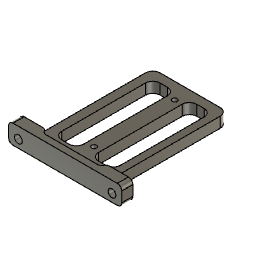
rs-25-5-90 (Autodesk Fusion 360 design; units mm, degrees)
Autodesk Fusion 360 part; units mm, degrees
mesh "Mesh1" [no effect]
sketch "Sketch1" plane through (0, 0, 0) normal (0, 0, 1) x (1, 0, 0)
  line L0 (25, 0) -> (-26, 0)
  line L1 (-26, 0) -> (-26, 78)
  line L2 (-26, 78) -> (25, 78)
  line L3 (25, 78) -> (25, 0)
  line L4 (-20, 5) -> (-5, 5)
  line L5 (-5, 5) -> (-5, 72)
  line L6 (-5, 72) -> (-20, 72)
  line L7 (-20, 72) -> (-20, 5)
  line L8 (0, 0) -> (0, 5) construction
  line L9 (20, 72) -> (20, 5)
  line L10 (5, 72) -> (20, 72)
  line L11 (5, 5) -> (5, 72)
  line L12 (20, 5) -> (5, 5)
  line L13 (0, 0) -> (0, 12) construction
  circle A0 centre (0, 12) radius 1.7
  line L14 (0, 12) -> (0, 39.5) construction
  line L15 (0, 39.5) -> (2, 39.5) construction
  circle A1 centre (0, 67) radius 1.7
  dimension "d1" = 51
  dimension "d2" = 78
  dimension "d3" = 67
  dimension "d4" = 12
  dimension "d5" = 3.4
  dimension "d6" = 27.5
  constraint horizontal L0
  constraint vertical L1
  constraint horizontal L2
  constraint vertical L3
  constraint horizontal L4
  constraint vertical L5
  constraint horizontal L6
  constraint vertical L7
  constraint coincident L8.start L13.start
  constraint perpendicular L0 L8
  constraint symmetric L4.start L8 L9.end
  constraint symmetric L4.end L8 L11.start
  constraint symmetric L5.end L8 L10.start
  constraint symmetric L6.end L8 L9.start
  constraint perpendicular L0 L13
  constraint coincident L13.end A0.centre
  constraint parallel L11 L14
  constraint perpendicular L14 L15
  constraint symmetric A0 L15 A1
  measures "d1" distance of L0.start L0.end
  measures "d2" distance of L0.start L2.end
  measures "d3" distance of L4.start L6.end
  measures "d4" distance of L8.start L13.end
  measures "d5" diameter of A0
  measures "d6" distance of L13.end L14.end
extrude "Extrude1" add sketch "Sketch1" along normal blind 7
sketch "Sketch2" plane through (0, 0, 0) normal (0, 1, 0) x (1, 0, 0)
  line L0 (38.4772, 0.1346) -> (-38.5893, 0.1346)
  line L1 (-38.5893, 0.1346) -> (-38.5893, -12.8654)
  line L2 (-38.5893, -12.8654) -> (38.4772, -12.8654)
  line L3 (38.4772, -12.8654) -> (38.4772, 0.1346)
  circle A0 centre (-31.8892, -5.2424) radius 2.65
  line L4 (0, 0) -> (0, -9) construction
  circle A1 centre (31.8892, -5.2424) radius 2.65
  dimension "d9" = 13
  dimension "d10" = 5.3
  constraint horizontal L0
  constraint vertical L1
  constraint horizontal L2
  constraint vertical L3
  constraint coincident L4.start origin
  constraint perpendicular L0 L4
  constraint symmetric A0 L4 A1
  measures "d9" distance of L0.end L1.end
  measures "d10" diameter of A0
extrude "Extrude2" add sketch "Sketch2" against normal blind 7.6
sketch "Sketch3" plane through (0, 0, 0) normal (0, 1, 0) x (-1, 0, 0)
  line L0 (-38.4772, 12.8654) -> (-38.4772, -0.1346)
  line L1 (-38.4772, -0.1346) -> (38.5893, -0.1346)
  line L2 (38.5893, -0.1346) -> (38.5893, 12.8654)
  line L3 (38.5893, 12.8654) -> (-38.4772, 12.8654)
  circle A0 centre (-31.8892, 5.2424) radius 2.65
  circle A1 centre (31.8892, 5.2424) radius 2.65
  line L4 (26, 7) -> (26, 0)
  line L5 (26, 0) -> (-25, 0)
  line L6 (-25, 0) -> (-25, 7)
  line L7 (-25, 7) -> (26, 7)
  circle A2 centre (-31.8892, 5.2424) radius 5.25
  line L8 (0, 0) -> (0, 11.9624) construction
  circle A3 centre (31.8892, 5.2424) radius 5.25
  line L9 (35.0019, 1.9981) -> (29.0019, 1.9981)
  line L10 (29.0019, 1.9981) -> (29.0019, -2.0108)
  line L11 (29.0019, -2.0108) -> (35.0019, -2.0108)
  line L12 (35.0019, -2.0108) -> (35.0019, 1.9981)
  line L13 (-35.0019, -2.0108) -> (-35.0019, 1.9981)
  line L14 (-35.0019, 1.9981) -> (-29.0019, 1.9981)
  line L15 (-29.0019, 1.9981) -> (-29.0019, -2.0108)
  line L16 (-29.0019, -2.0108) -> (-35.0019, -2.0108)
  point P0 (32.0019, -0.0064)
  dimension "d13" = 10.5
  dimension "d26" = 6
  constraint concentric A0 A2
  constraint coincident L8.start origin
  constraint perpendicular L7 L8
  constraint symmetric A2 L8 A3
  constraint perpendicular L9 L10
  constraint parallel L9 L11
  constraint parallel L10 L12
  constraint horizontal L9
  constraint coincident A3 P0
  constraint symmetric L8 L9.start L13.end
  constraint symmetric L8 L9.end L14.end
  constraint symmetric L8 L10.end L15.end
  constraint symmetric L8 L11.end L13.start
  measures "d13" diameter of A2
  measures "d26" distance of L10.end L11.end
extrude "Extrude6" cut sketch "Sketch3" against normal blind 3 contours L1 A2 L13 L15 | A2 L13 L14 L15 | L1 A3 L10 L12 | A3 L9 L10 L12 picked at (-32.1282, 1.3372) picked at (32.1282, 1.3372)
extrude "Extrude3" cut sketch "Sketch3" against normal blind 3 contours A2 L13 L14 L15 | A2 L13 L14 L15 | A3 L9 L10 L12 | A3 L9 L10 L12
sketch "Sketch4" plane through (0, 0, 0) normal (0, 0, -1) x (1, 0, 0)
  line L0 (20, -5) -> (20, -72)
  line L1 (20, -72) -> (5, -72)
  line L2 (5, -72) -> (5, -5)
  line L3 (5, -5) -> (20, -5)
  circle A0 centre (0, -67) radius 1.7
  line L4 (-20, -72) -> (-20, -5)
  line L5 (-20, -5) -> (-5, -5)
  line L6 (-5, -5) -> (-5, -72)
  line L7 (-5, -72) -> (-20, -72)
  circle A1 centre (0, -12) radius 1.7
  line L8 (-26, -78) -> (25, -78)
  line L9 (25, -78) -> (25, 0)
  line L10 (25, 0) -> (-26, 0)
  line L11 (-26, 0) -> (-26, -78)
  circle A2 centre (0, -67) radius 3.6
  line L12 (-3.0129, -39.5) -> (3.0263, -39.5) construction
  circle A3 centre (0, -12) radius 3.6
  point P0 (0, -39.5)
  dimension "d16" = 7.2
  dimension "d17" = 27.5
  constraint concentric A0 A2
  constraint horizontal L12
  constraint symmetric A2 L12 A3
  measures "d16" diameter of A2
  measures "d17" distance of A0.centre P0
extrude "Extrude4" cut sketch "Sketch4" against normal blind 3 contours A2 | A3
sketch "Sketch5" plane through (0, 0, 12.8654) normal (0, 0, 1) x (-1, 0, 0)
  line L0 (-38.4772, 0) -> (38.5893, 0)
  line L1 (38.5893, 0) -> (38.5893, 7.6)
  line L2 (38.5893, 7.6) -> (-38.4772, 7.6)
  line L3 (-38.4772, 7.6) -> (-38.4772, 0)
  line L4 (20.6012, 3.1769) -> (-20.6012, 3.1769)
  line L5 (-20.6012, 3.1769) -> (-20.6012, -3.1769)
  line L6 (-20.6012, -3.1769) -> (20.6012, -3.1769)
  line L7 (20.6012, -3.1769) -> (20.6012, 3.1769)
  line L8 (20.6012, 3.1769) -> (-20.6012, -3.1769) construction
  line L9 (-20.6012, 3.1769) -> (20.6012, -3.1769) construction
  constraint perpendicular L4 L5
  constraint parallel L4 L6
  constraint parallel L5 L7
  constraint horizontal L4
  constraint coincident L8 origin
  constraint coincident L9 origin
extrude "Extrude5" cut sketch "Sketch5" against normal up to surface (5.8654 mm away) contours L0 L4 L5 L7 | L0 L5 L6 L7
fillet "Fillet1" radius 5 2 edges at (-26, 78, 3.5) (25, 78, 3.5)
fillet "Fillet1" radius 5 8 edges at (20, 72, 3.5) (-5, 72, 3.5) (5, 72, 3.5) (-20, 72, 3.5) (-20, 5, 3.5) (5, 5, 3.5) (20, 5, 3.5) (-5, 5, 3.5)
fillet "Fillet1" radius 3 4 edges at (20.6012, 0, 9.9327) (20.6012, -3.1769, 9.9327) (-20.6012, 0, 9.9327) (-20.6012, -3.1769, 9.9327)
fillet "Fillet1" radius 3 4 edges at (38.4772, -3.8, 12.8654) (38.4772, -3.8, -0.1346) (-38.5893, -3.8, 12.8654) (-38.5893, -3.8, -0.1346)
fillet "Fillet2" radius 0.3 12 edges at (31.7518, 0, 10.4906) (31.7518, -3, 10.4906) (29.0019, -1.5, 0.8576) (29.0019, -1.5, -0.1346) (35.0019, -1.5, 1.0147) (35.0019, -1.5, -0.1346) (-29.0019, -1.5, 0.8576) (-35.0019, -1.5, 1.0147) (-31.7518, -3, 10.4906) (-31.7518, 0, 10.4906) (-29.0019, -1.5, -0.1346) (-35.0019, -1.5, -0.1346)
extrude "Extrude7" add 1 faces at (-3.1971, 75.9325, 0) along direction (0, 0, -1) up to surface (0.1346 mm away)
fillet "Fillet3" radius 2 2 edges at (-3.3564, 10.6982, 3) (-3.3564, 65.6982, 3)
